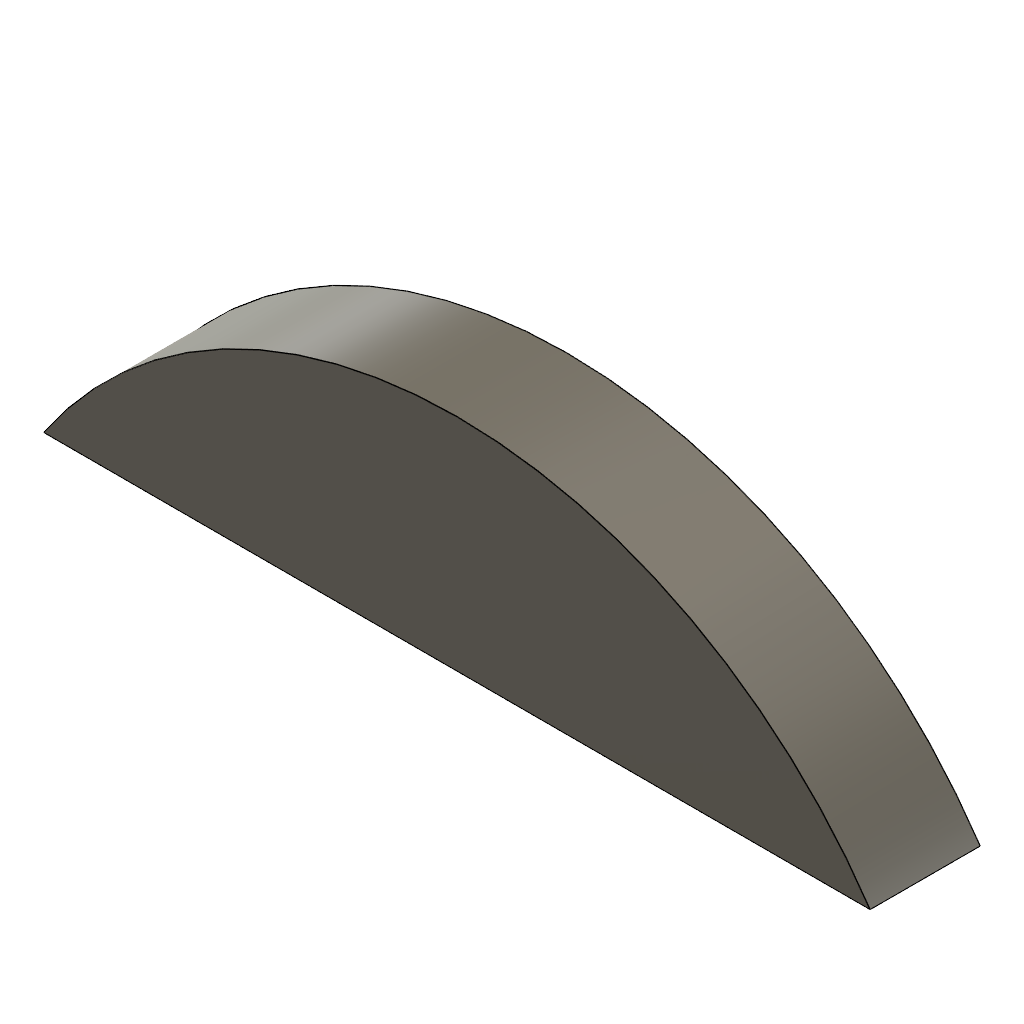
sk_arc_three_point (Autodesk Fusion 360 design; units mm, degrees)
part number: 2026-11-13-14-35-13-867
Autodesk Fusion 360 part; units mm, degrees
sketch "Sketch1" plane through (0, 0, 0) normal (0, 0, 1) x (1, 0, 0)
  arc A0 (30, 0) -> (0, 0) centre (15, -10.0625) ccw
  line L0 (30, 0) -> (0, 0)
extrude "Extrude1" add sketch "Sketch1" along normal blind 4
